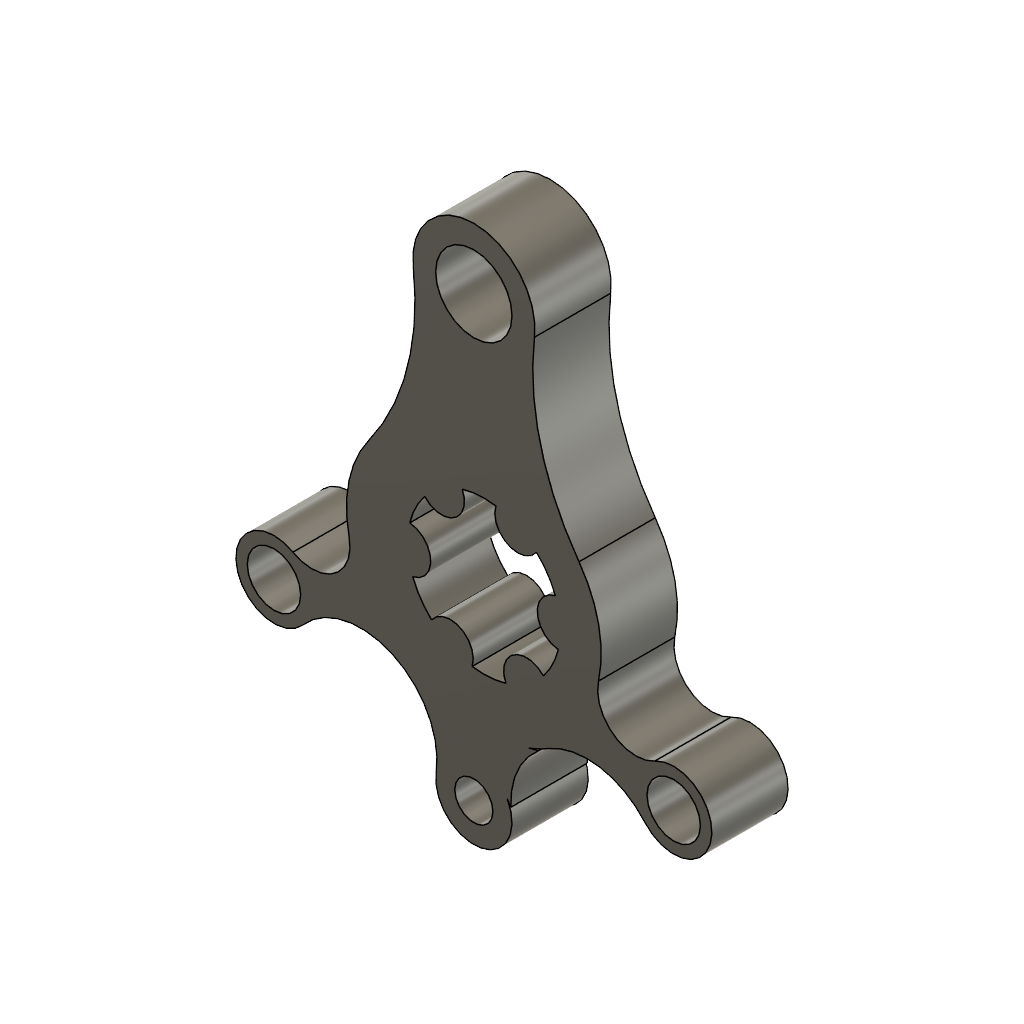
26015028 exercise 1.1(nithish R) (Autodesk Fusion 360 design; units mm, degrees)
part number: 2026-09-22-15-13-25-935
Autodesk Fusion 360 part; units mm, degrees
sketch "Sketch1" plane through (0, 0, 0) normal (0, 0, 1) x (1, 0, 0)
  circle A0 centre (-2.6722, 65) radius 10
  circle A1 centre (49.6903, -26) radius 7
  circle A2 centre (-2.6722, -50) radius 5
  arc A3 (13.2136, 63.0919) -> (24.8811, 17.9775) centre (76.7569, 55.4596) ccw
  arc A4 (29.9975, -6.5123) -> (44.7301, -17.3169) centre (39.7699, -8.6338) ccw
  arc A5 (42.1297, -32.545) -> (7.2213, -48.545) centre (27.0085, -45.6351) ccw
  arc A6 (29.9975, -6.5123) -> (24.8811, 17.9775) centre (0, 0) ccw
  arc A7 (11.7528, -30.8667) -> (16.8221, -28.4235) centre (0, 0) ccw
  arc A8 (42.1297, -32.545) -> (44.7301, -17.3169) centre (49.6903, -26) ccw
  arc A9 (14.2008, -30.274) -> (11.7528, -30.8667) centre (15.3111, -40.2122) ccw
  arc A10 (6.1111, -45.2195) -> (7.0333, -46.6302) centre (15.3111, -40.2122) ccw
  arc A11 (-30.2256, 17.9775) -> (-18.5581, 63.0919) centre (-82.1013, 55.4596) ccw
  arc A12 (-30.2256, 17.9775) -> (-35.342, -6.5123) centre (-5.3445, 0) ccw
  arc A13 (-50.0746, -17.3169) -> (-35.342, -6.5123) centre (-45.1143, -8.6338) ccw
  arc A14 (-50.0746, -17.3169) -> (-47.4742, -32.545) centre (-55.0348, -26) ccw
  circle A15 centre (-55.0348, -26) radius 7
  arc A16 (-12.5658, -48.545) -> (-47.4742, -32.545) centre (-32.353, -45.6351) ccw
  arc A17 (13.2136, 63.0919) -> (-18.5581, 63.0919) centre (-2.6722, 65) ccw
  arc A18 (-12.5658, -48.545) -> (6.1111, -45.2195) centre (-2.6722, -50) ccw
  arc A19 (3.106, 19.7573) -> (13.7524, 14.5214) centre (8.8264, 17.947) ccw
  arc A20 (-15.5574, 12.5686) -> (-5.6997, 19.1706) centre (-11.1294, 16.6174) ccw
  arc A21 (-18.6634, -7.1888) -> (-19.4521, 4.6492) centre (-19.9558, -1.3296) ccw
  arc A22 (-3.106, -19.7573) -> (-13.7524, -14.5214) centre (-8.8264, -17.947) ccw
  arc A23 (15.5574, -12.5686) -> (5.6997, -19.1706) centre (11.1294, -16.6174) ccw
  arc A24 (18.6634, 7.1888) -> (19.4521, -4.6492) centre (19.9558, 1.3296) ccw
  arc A25 (3.106, 19.7573) -> (-5.6997, 19.1706) centre (0, 0) ccw
  arc A26 (-15.5574, 12.5686) -> (-19.4521, 4.6492) centre (0, 0) ccw
  arc A27 (-18.6634, -7.1888) -> (-13.7524, -14.5214) centre (0, 0) ccw
  arc A28 (18.6634, 7.1888) -> (13.7524, 14.5214) centre (0, 0) ccw
  arc A29 (-3.106, -19.7573) -> (5.6997, -19.1706) centre (0, 0) ccw
  arc A30 (15.5574, -12.5686) -> (19.4521, -4.6492) centre (0, 0) ccw
  dimension "d1" = 20
  dimension "d2" = 32
  dimension "d3" = 32
  dimension "d4" = 32
  dimension "d5" = 40
  dimension "d8" = 40
  dimension "d9" = 65
  dimension "d10" = 14
  dimension "d11" = 20
  dimension "d12" = 10
  dimension "d13" = 20
  dimension "d14" = 26
  dimension "d15" = 24
  dimension "d17" = 20
  dimension "d18" = 40
  dimension "d19" = 20
  dimension "d20" = 12
  dimension "d22" = 360
  constraint concentric A0 A17
  constraint coincident A6.centre A7.centre
  constraint concentric A1 A8
  constraint concentric A2 A18
  constraint tangent A3 A17
  constraint tangent A3 A6
  constraint tangent A4 A6
  constraint tangent A4 A8
  constraint tangent A3 A4
  constraint tangent A5 A8
  constraint tangent A5 A18
  constraint tangent A5 A7
  constraint coincident A5.end A18
  constraint tangent A10 A18
  constraint tangent A7 A9
  constraint coincident A5 A7.end
  constraint concentric A6 A7
  constraint coincident A5 A10.end
  constraint coincident A5 A9.start
  constraint concentric A9 A10
  constraint tangent A11 A17
  constraint coincident A19.centre A25
  constraint concentric A25 A26
  constraint concentric A26 A27
  constraint concentric A27 A29
  constraint concentric A28 A30
  constraint concentric A29 A30
  measures "d1" diameter of A0
  measures "d2" diameter of A17
  measures "d3" diameter of A17
  measures "d4" diameter of A17
  measures "d5" diameter of A25
  measures "d8" diameter of A25
  measures "d9" vertical distance of A0.centre A6.centre
  measures "d10" diameter of A1
  measures "d11" diameter of A8
  measures "d12" diameter of A2
  measures "d13" diameter of A18
  measures "d14" vertical distance of A1.centre A6.centre
  measures "d15" vertical distance of A1.centre A2.centre
  measures "d17" diameter of A4
  measures "d18" diameter of A5
  measures "d19" diameter of A9
  measures "d20" diameter of A19
extrude "Extrude1" add sketch "Sketch1" against normal blind 20 contours A3 A4 A5 A6 A7 A8 A9 A10 A11 A12 A13 A14 A16 A17 A18
